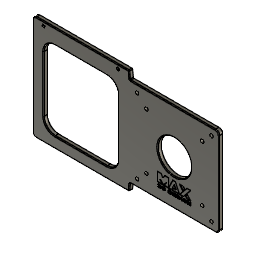
OFFSET VESA MOUNT (Autodesk Fusion 360 design; units mm, degrees)
part number: 2026-05-18-19-14-02-134
Autodesk Fusion 360 part; units mm, degrees
sketch "Sketch1" plane through (0, 0, 0) normal (0, 1, 0) x (1, 0, 0)
  line L0 (0, -120) -> (1, -120)
  line L1 (1, -120) -> (1, 0)
  line L2 (1, 0) -> (0, 0)
  line L3 (1, -120) -> (121, -120)
  line L4 (121, -120) -> (121, 0)
  line L5 (121, 0) -> (1, 0)
  line L6 (1, 0) -> (1, -120)
  line L7 (11, -110) -> (111, -110)
  line L8 (111, -110) -> (111, -10)
  line L9 (111, -10) -> (11, -10)
  line L10 (11, -10) -> (11, -110)
  line L11 (98.5, -97.5) -> (23.5, -97.5)
  line L12 (23.5, -97.5) -> (23.5, -22.5)
  line L13 (23.5, -22.5) -> (98.5, -22.5)
  line L14 (98.5, -22.5) -> (98.5, -97.5)
  line L15 (61, -97.5) -> (61, -110)
  line L16 (98.5, -60) -> (111, -60)
  line L17 (111, -60) -> (121, -60)
  line L18 (61, -120) -> (61, -110)
  line L19 (0, -120) -> (0, 0)
  line L20 (0, -130.5) -> (-129.5, -130.5)
  line L21 (-129.5, -130.5) -> (-129.5, 10.5)
  line L22 (-129.5, 10.5) -> (0, 10.5)
  line L23 (0, 10.5) -> (0, -130.5)
  line L24 (0, -130.5) -> (1, -120)
  line L25 (0, 10.5) -> (1, 0)
  circle A0 centre (61, -60) radius 22.5
  line L26 (-14.75, -125) -> (-114.75, -125)
  line L27 (-64.75, -130.5) -> (-64.75, -125)
  circle A1 centre (-114.75, -125) radius 2
  circle A2 centre (-14.75, -125) radius 2
  line L28 (-14.75, -4.5) -> (-114.75, -4.5)
  line L29 (-114.75, -4.5) -> (-114.75, -110)
  line L30 (-114.75, -110) -> (-14.75, -110)
  line L31 (-14.75, -110) -> (-14.75, -4.5)
  point P0 (122.7782, -63.5)
  point P1 (0, -60)
  point P2 (0, -60)
  dimension "d7" = 10
  dimension "d8" = 10
  dimension "d9" = 75
  dimension "d10" = 100
  dimension "d12" = 1
  dimension "d13" = 129.5
  dimension "d14" = 141
  dimension "d15" = 45
  dimension "d18" = 5.5
  dimension "d19" = 100
  dimension "d20" = 4
  dimension "d32" = 15
  dimension "d33" = 15
  constraint horizontal L0
  constraint vertical L1
  constraint horizontal L2
  constraint horizontal L3
  constraint vertical L4
  constraint horizontal L5
  constraint vertical L6
  constraint horizontal L7
  constraint vertical L8
  constraint horizontal L9
  constraint vertical L10
  constraint horizontal L11
  constraint vertical L12
  constraint horizontal L13
  constraint vertical L14
  constraint midpoint L11 L15.start
  constraint midpoint L7 L15.end
  constraint midpoint L14 L16.start
  constraint midpoint L8 L16.end
  constraint midpoint L4 L17.end
  constraint vertical L15
  constraint horizontal L16
  constraint horizontal L17
  constraint midpoint L3 L18.start
  constraint vertical L18
  constraint collinear L2 L5
  constraint equal L11 L14
  constraint equal L7 L8
  constraint perpendicular L2 L19
  constraint coincident L2.end L19.end
  constraint horizontal L20
  constraint vertical L21
  constraint horizontal L22
  constraint vertical L23
  constraint coincident L23 P2
  constraint midpoint L23 P2
  constraint midpoint L19 P2
  constraint coincident P2 P1
  constraint vertical L15.start A0.centre
  constraint horizontal L16.start A0.centre
  constraint horizontal L26
  constraint midpoint L20 L27.start
  constraint midpoint L26 L27.end
  constraint vertical L27
  constraint coincident L26.end A1.centre
  constraint coincident L26.start A2.centre
  constraint equal A1 A2
  constraint horizontal L28
  constraint vertical L29
  constraint horizontal L30
  constraint vertical L31
  constraint vertical L26.end L29.end
  constraint vertical L26.start L30.end
  measures "d7" distance of L4 L8
  measures "d8" distance of L3 L7
  measures "d9" distance of L11.start L13.end
  measures "d10" distance of L7.end L8.end
  measures "d12" distance of L0.start L0.end
  measures "d13" distance of L21.end L22.end
  measures "d14" distance of L20.end L21.end
  measures "d15" diameter of A0
  measures "d18" distance of L27.start L27.end
  measures "d19" distance of L26.start L26.end
  measures "d20" diameter of A1
  measures "d32" distance of L22 L28
  measures "d33" distance of L26 L30
extrude "Extrude1" add sketch "Sketch1" along normal blind 6
hole "Hole1" at (23.5, 0, 97.5) at (98.5, 0, 97.5) at (111, 0, 110) at (11, 0, 110) at (11, 0, 10) at (23.5, 0, 22.5) at (98.5, 0, 22.5) at (111, 0, 10) direction (0, 1, 0) diameter 4.5 depth 30 tip angle 118
fillet "Fillet1" radius 5 4 edges at (121, 3, 120) (121, 3, 0) (-129.5, 3, -10.5) (-129.5, 3, 130.5)
sketch "Sketch2" plane through (0, 6, 0) normal (0, 1, 0) x (-1, 0, 0)
  arc A0 (129.5, 125.5) -> (124.5, 130.5) centre (124.5, 125.5) ccw
  line L0 (124.5, 130.5) -> (0, 130.5)
  line L1 (0, 130.5) -> (-1, 120)
  line L2 (-1, 120) -> (-116, 120)
  arc A1 (-116, 120) -> (-121, 115) centre (-116, 115) ccw
  line L3 (-121, 115) -> (-121, 5)
  arc A2 (-121, 5) -> (-116, 0) centre (-116, 5) ccw
  line L4 (-116, 0) -> (-1, 0)
  line L5 (-1, 0) -> (0, -10.5)
  line L6 (0, -10.5) -> (124.5, -10.5)
  arc A3 (124.5, -10.5) -> (129.5, -5.5) centre (124.5, -5.5) ccw
  line L7 (129.5, -5.5) -> (129.5, 125.5)
  circle A4 centre (14.75, 125) radius 2
  circle A5 centre (-61, 60) radius 22.5
  circle A6 centre (114.75, 125) radius 2
  circle A7 centre (-111, 10) radius 2.25
  circle A8 centre (-23.5, 22.5) radius 2.25
  circle A9 centre (-11, 110) radius 2.25
  circle A10 centre (-98.5, 97.5) radius 2.25
  circle A11 centre (-23.5, 97.5) radius 2.25
  circle A12 centre (-111, 110) radius 2.25
  circle A13 centre (-11, 10) radius 2.25
  circle A14 centre (-98.5, 22.5) radius 2.25
  circle A15 centre (14.75, 125) radius 2.75
  circle A16 centre (114.75, 125) radius 2.75
  line L8 (14.75, 4.5) -> (14.75, 110)
  line L9 (14.75, 110) -> (114.75, 110)
  line L10 (114.75, 110) -> (114.75, 4.5)
  line L11 (114.75, 4.5) -> (14.75, 4.5)
  dimension "d29" = 5.5
  constraint concentric A4 A15
  constraint concentric A6 A16
  constraint equal A15 A16
  measures "d29" diameter of A15
extrude "Extrude2" cut sketch "Sketch2" against normal blind 4.5 contours A4 | A6 | A15 | A16
fillet "Fillet2" radius 15 4 edges at (-114.75, 3, 110) (-14.75, 3, 110) (-14.75, 3, 4.5) (-114.75, 3, 4.5)
fillet "Fillet3" radius 1 4 edges at (0, 3, 130.5) (1, 3, 120) (1, 3, 0) (0, 3, -10.5)
chamfer "Chamfer1" distance 1 angle 45 50 edges at (-14.75, 0, 57.25) (-19.1434, 0, 105.6066) (-64.75, 0, 110) (-110.3566, 0, 105.6066) (-114.75, 0, 57.25) (-110.3566, 0, 8.8934) (-64.75, 0, 4.5) (-19.1434, 0, 8.8934) (0.5, 0, -5.25) (1.2365, 0, -0.2601) (58.9546, 0, 0) (119.5355, 0, 1.4645) (121, 0, 60) (119.5355, 0, 118.5355) (58.9546, 0, 120) (1.2365, 0, 120.2601) (0.5, 0, 125.25) (-0.2365, 0, 130.2399) (-62.7046, 0, 130.5) (-128.0355, 0, 129.0355) (-129.5, 0, 60) (-128.0355, 0, -9.0355) (-62.7046, 0, -10.5) (-0.2365, 0, -10.2399) (0.5, 6, -5.25) (-0.2365, 6, -10.2399) (-62.7046, 6, -10.5) (-128.0355, 6, -9.0355) (-129.5, 6, 60) (-128.0355, 6, 129.0355) (-62.7046, 6, 130.5) (-0.2365, 6, 130.2399) (0.5, 6, 125.25) (1.2365, 6, 120.2601) (58.9546, 6, 120) (119.5355, 6, 118.5355) (121, 6, 60) (119.5355, 6, 1.4645) (58.9546, 6, 0) (1.2365, 6, -0.2601) (40.0226, 0, 51.8637) (40.0226, 6, 51.8637) (-14.75, 6, 57.25) (-19.1434, 6, 105.6066) (-64.75, 6, 110) (-110.3566, 6, 105.6066) (-114.75, 6, 57.25) (-110.3566, 6, 8.8934) (-64.75, 6, 4.5) (-19.1434, 6, 8.8934)
sketch "Sketch3" plane through (0, 0, 0) normal (0, -1, 0) x (1, 0, 0)
  line L0 (-0.9093, 129.5) -> (-124.5, 129.5)
  arc A0 (-124.5, 129.5) -> (-128.5, 125.5) centre (-124.5, 125.5) ccw
  line L1 (-128.5, 125.5) -> (-128.5, -5.5)
  arc A1 (-128.5, -5.5) -> (-124.5, -9.5) centre (-124.5, -5.5) ccw
  line L2 (-124.5, -9.5) -> (-0.9093, -9.5)
  line L3 (-0.9093, -9.5) -> (-0.0817, -0.8104)
  arc A2 (1.9093, 1) -> (-0.0817, -0.8104) centre (1.9093, -1) ccw
  line L4 (1.9093, 1) -> (116, 1)
  arc A3 (116, 1) -> (120, 5) centre (116, 5) ccw
  line L5 (120, 5) -> (120, 115)
  arc A4 (120, 115) -> (116, 119) centre (116, 115) ccw
  line L6 (116, 119) -> (1.9093, 119)
  arc A5 (-0.0817, 120.8104) -> (1.9093, 119) centre (1.9093, 121) ccw
  line L7 (-0.0817, 120.8104) -> (-0.9093, 129.5)
  circle A6 centre (98.5, 22.5) radius 2.25
  circle A7 centre (11, 10) radius 2.25
  circle A8 centre (111, 110) radius 2.25
  circle A9 centre (23.5, 97.5) radius 2.25
  circle A10 centre (98.5, 97.5) radius 2.25
  circle A11 centre (11, 110) radius 2.25
  circle A12 centre (23.5, 22.5) radius 2.25
  circle A13 centre (111, 10) radius 2.25
  circle A14 centre (-114.75, 125) radius 2
  circle A15 centre (-14.75, 125) radius 2
  line L8 (-13.75, 95) -> (-13.75, 19.5)
  arc A16 (-29.75, 3.5) -> (-13.75, 19.5) centre (-29.75, 19.5) ccw
  line L9 (-29.75, 3.5) -> (-99.75, 3.5)
  arc A17 (-115.75, 19.5) -> (-99.75, 3.5) centre (-99.75, 19.5) ccw
  line L10 (-115.75, 19.5) -> (-115.75, 95)
  arc A18 (-99.75, 111) -> (-115.75, 95) centre (-99.75, 95) ccw
  line L11 (-99.75, 111) -> (-29.75, 111)
  arc A19 (-13.75, 95) -> (-29.75, 111) centre (-29.75, 95) ccw
  circle A20 centre (61, 60) radius 23.5
  line L12 (43.0359, 15.5581) -> (43.0359, 15.4087)
  spline S0 degree 3 poles (43.0359, 15.4087) (43.0359, 14.8683) (42.6052, 14.478) (42.0137, 14.478) knots 0 0 0 0 1 1 1 1
  line L13 (42.0137, 14.478) -> (39.4564, 14.478)
  spline S1 degree 3 poles (39.4564, 14.478) (38.9762, 14.478) (38.6317, 14.7746) (38.6317, 15.1808) knots 0 0 0 0 1 1 1 1
  line L14 (38.6317, 15.1808) -> (38.6317, 15.5353)
  line L15 (38.6317, 15.5353) -> (40.0975, 16.0429)
  line L16 (40.0975, 16.0429) -> (40.0975, 15.6427)
  spline S2 degree 3 poles (40.0975, 15.6427) (40.0975, 15.4933) (40.2057, 15.4087) (40.3963, 15.4087) knots 0 0 0 0 1 1 1 1
  line L17 (40.3963, 15.4087) -> (41.2706, 15.4087)
  spline S3 degree 3 poles (41.2706, 15.4087) (41.4611, 15.4087) (41.5694, 15.4933) (41.5694, 15.6427) knots 0 0 0 0 1 1 1 1
  line L18 (41.5694, 15.6427) -> (41.5694, 15.7403)
  spline S4 degree 3 poles (41.5694, 15.7403) (41.5694, 15.8897) (41.4611, 15.9743) (41.2706, 15.9743) knots 0 0 0 0 1 1 1 1
  line L19 (41.2706, 15.9743) -> (40.6166, 15.9743)
  line L20 (40.6166, 15.9743) -> (40.6166, 16.69)
  line L21 (40.6166, 16.69) -> (41.1722, 16.69)
  spline S5 degree 3 poles (41.1722, 16.69) (41.3628, 16.69) (41.471, 16.7747) (41.471, 16.9241) knots 0 0 0 0 1 1 1 1
  line L22 (41.471, 16.9241) -> (41.471, 17.0216)
  spline S6 degree 3 poles (41.471, 17.0216) (41.471, 17.171) (41.3628, 17.2556) (41.1722, 17.2556) knots 0 0 0 0 1 1 1 1
  line L23 (41.1722, 17.2556) -> (40.3963, 17.2556)
  spline S7 degree 3 poles (40.3963, 17.2556) (40.2057, 17.2556) (40.0975, 17.171) (40.0975, 17.0216) knots 0 0 0 0 1 1 1 1
  line L24 (40.0975, 17.0216) -> (40.0975, 16.8494)
  line L25 (40.0975, 16.8494) -> (38.6317, 17.357)
  line L26 (38.6317, 17.357) -> (38.6317, 17.4843)
  spline S8 degree 3 poles (38.6317, 17.4843) (38.6317, 17.8913) (38.977, 18.1871) (39.4564, 18.1871) knots 0 0 0 0 1 1 1 1
  line L27 (39.4564, 18.1871) -> (41.9482, 18.184)
  spline S9 degree 3 poles (41.9482, 18.184) (42.5397, 18.184) (42.9376, 17.7938) (42.9376, 17.2533) knots 0 0 0 0 1 1 1 1
  line L28 (42.9376, 17.2533) -> (42.9376, 17.0094)
  spline S10 degree 3 poles (42.9376, 17.0094) (42.9376, 16.6611) (42.76, 16.456) (42.481, 16.3455) knots 0 0 0 0 1 1 1 1
  spline S11 degree 3 poles (42.481, 16.3455) (42.8026, 16.2312) (43.0359, 15.9972) (43.0359, 15.5581) knots 0 0 0 0 1 1 1 1
  line L29 (48.7557, 17.2564) -> (48.7557, 15.4011)
  spline S12 degree 3 poles (48.7557, 15.4011) (48.7557, 14.8645) (48.325, 14.4773) (47.7335, 14.4773) knots 0 0 0 0 1 1 1 1
  line L30 (47.7335, 14.4773) -> (44.3515, 14.4773)
  line L31 (44.3515, 14.4773) -> (44.3515, 18.1871)
  line L32 (44.3515, 18.1871) -> (47.7335, 18.1871)
  spline S13 degree 3 poles (47.7335, 18.1871) (48.325, 18.1871) (48.7557, 17.7968) (48.7557, 17.2564) knots 0 0 0 0 1 1 1 1
  spline S14 degree 3 poles (47.2899, 16.876) (47.2899, 17.0384) (47.158, 17.1558) (46.9774, 17.1558) knots 0 0 0 0 1 1 1 1
  line L33 (46.9774, 17.1558) -> (45.85, 17.1626)
  line L34 (45.85, 17.1626) -> (45.85, 15.5033)
  line L35 (45.85, 15.5033) -> (46.9774, 15.5033)
  spline S15 degree 3 poles (46.9774, 15.5033) (47.158, 15.5033) (47.2899, 15.6168) (47.2899, 15.7769) knots 0 0 0 0 1 1 1 1
  line L36 (47.2899, 15.7769) -> (47.2899, 16.876)
  line L37 (57.0068, 17.2564) -> (57.0068, 15.4011)
  spline S16 degree 3 poles (57.0068, 15.4011) (57.0068, 14.8645) (56.5762, 14.4773) (55.9847, 14.4773) knots 0 0 0 0 1 1 1 1
  line L38 (55.9847, 14.4773) -> (52.6027, 14.4773)
  line L39 (52.6027, 14.4773) -> (52.6027, 18.1871)
  line L40 (52.6027, 18.1871) -> (55.9847, 18.1871)
  spline S17 degree 3 poles (55.9847, 18.1871) (56.5762, 18.1871) (57.0068, 17.7968) (57.0068, 17.2564) knots 0 0 0 0 1 1 1 1
  spline S18 degree 3 poles (55.5403, 16.876) (55.5403, 17.0384) (55.4084, 17.1558) (55.2278, 17.1558) knots 0 0 0 0 1 1 1 1
  line L41 (55.2278, 17.1558) -> (54.1004, 17.1626)
  line L42 (54.1004, 17.1626) -> (54.1004, 15.5033)
  line L43 (54.1004, 15.5033) -> (55.2278, 15.5033)
  spline S19 degree 3 poles (55.2278, 15.5033) (55.4084, 15.5033) (55.5403, 15.6168) (55.5403, 15.7769) knots 0 0 0 0 1 1 1 1
  line L44 (55.5403, 15.7769) -> (55.5403, 16.876)
  line L45 (58.5526, 18.1871) -> (62.6938, 18.1871)
  line L46 (62.6938, 18.1871) -> (62.6938, 17.2274)
  line L47 (62.6938, 17.2274) -> (60.0512, 17.2274)
  line L48 (60.0512, 17.2274) -> (60.0512, 16.7716)
  line L49 (60.0512, 16.7716) -> (61.7738, 16.7716)
  line L50 (61.7738, 16.7716) -> (61.7738, 15.8928)
  line L51 (61.7738, 15.8928) -> (60.0512, 15.8928)
  line L52 (60.0512, 15.8928) -> (60.0512, 15.4369)
  line L53 (60.0512, 15.4369) -> (62.6938, 15.4369)
  line L54 (62.6938, 15.4369) -> (62.6938, 14.4773)
  line L55 (62.6938, 14.4773) -> (58.5526, 14.4773)
  line L56 (58.5526, 14.4773) -> (58.5526, 18.1871)
  line L57 (63.9104, 15.1801) -> (63.9104, 15.2776)
  line L58 (63.9104, 15.2776) -> (65.3761, 15.7853)
  line L59 (65.3761, 15.7853) -> (65.3761, 15.5772)
  spline S20 degree 3 poles (65.3761, 15.5772) (65.3761, 15.4278) (65.4844, 15.3432) (65.6749, 15.3432) knots 0 0 0 0 1 1 1 1
  line L60 (65.6749, 15.3432) -> (66.5462, 15.3432)
  spline S21 degree 3 poles (66.5462, 15.3432) (66.7367, 15.3432) (66.845, 15.4278) (66.845, 15.5772) knots 0 0 0 0 1 1 1 1
  line L61 (66.845, 15.5772) -> (66.845, 15.6488)
  spline S22 degree 3 poles (66.845, 15.6488) (66.845, 15.7982) (66.7367, 15.8828) (66.5462, 15.8828) knots 0 0 0 0 1 1 1 1
  line L62 (66.5462, 15.8828) -> (64.9325, 15.8828)
  spline S23 degree 3 poles (64.9325, 15.8828) (64.341, 15.8828) (63.9104, 16.2731) (63.9104, 16.8135) knots 0 0 0 0 1 1 1 1
  line L63 (63.9104, 16.8135) -> (63.9104, 17.4835)
  spline S24 degree 3 poles (63.9104, 17.4835) (63.9104, 17.8906) (64.2519, 18.1863) (64.729, 18.1863) knots 0 0 0 0 1 1 1 1
  line L64 (64.729, 18.1863) -> (67.4898, 18.1863)
  spline S25 degree 3 poles (67.4898, 18.1863) (67.97, 18.1863) (68.3145, 17.8898) (68.3145, 17.4835) knots 0 0 0 0 1 1 1 1
  line L65 (68.3145, 17.4835) -> (68.3145, 17.386)
  line L66 (68.3145, 17.386) -> (66.8488, 16.8783)
  line L67 (66.8488, 16.8783) -> (66.8488, 17.0864)
  spline S26 degree 3 poles (66.8488, 17.0864) (66.8488, 17.2358) (66.7405, 17.3204) (66.55, 17.3204) knots 0 0 0 0 1 1 1 1
  line L68 (66.55, 17.3204) -> (65.6787, 17.3204)
  spline S27 degree 3 poles (65.6787, 17.3204) (65.4882, 17.3204) (65.38, 17.2358) (65.38, 17.0864) knots 0 0 0 0 1 1 1 1
  line L69 (65.38, 17.0864) -> (65.38, 17.0148)
  spline S28 degree 3 poles (65.38, 17.0148) (65.38, 16.8654) (65.4882, 16.7808) (65.6787, 16.7808) knots 0 0 0 0 1 1 1 1
  line L70 (65.6787, 16.7808) -> (67.2924, 16.7808)
  spline S29 degree 3 poles (67.2924, 16.7808) (67.8839, 16.7808) (68.3145, 16.3905) (68.3145, 15.8501) knots 0 0 0 0 1 1 1 1
  line L71 (68.3145, 15.8501) -> (68.3145, 15.1793)
  spline S30 degree 3 poles (68.3145, 15.1793) (68.3145, 14.7723) (67.9693, 14.4765) (67.4959, 14.4765) knots 0 0 0 0 1 1 1 1
  line L72 (67.4959, 14.4765) -> (64.7351, 14.4765)
  spline S31 degree 3 poles (64.7351, 14.4765) (64.2557, 14.4773) (63.9104, 14.7738) (63.9104, 15.1801) knots 0 0 0 0 1 1 1 1
  line L73 (69.762, 18.1871) -> (71.2606, 18.1871)
  line L74 (71.2606, 18.1871) -> (71.2606, 14.4773)
  line L75 (71.2606, 14.4773) -> (69.762, 14.4773)
  line L76 (69.762, 14.4773) -> (69.762, 18.1871)
  line L77 (72.8056, 15.174) -> (72.8056, 17.4843)
  spline S32 degree 3 poles (72.8056, 17.4843) (72.8056, 17.8913) (73.1509, 18.1871) (73.6243, 18.1871) knots 0 0 0 0 1 1 1 1
  line L78 (73.6243, 18.1871) -> (76.3851, 18.1871)
  spline S33 degree 3 poles (76.3851, 18.1871) (76.8645, 18.1871) (77.2098, 17.8906) (77.2098, 17.4843) knots 0 0 0 0 1 1 1 1
  line L79 (77.2098, 17.4843) -> (77.2098, 17.3928)
  line L80 (77.2098, 17.3928) -> (75.744, 16.8852)
  spline S34 degree 3 poles (75.744, 16.8852) (75.744, 17.0445) (75.616, 17.1588) (75.4384, 17.1588) knots 0 0 0 0 1 1 1 1
  line L81 (75.4384, 17.1588) -> (74.577, 17.1588)
  spline S35 degree 3 poles (74.577, 17.1588) (74.3994, 17.1588) (74.2714, 17.0414) (74.2714, 16.8791) knots 0 0 0 0 1 1 1 1
  line L82 (74.2714, 16.8791) -> (74.2714, 15.7792)
  spline S36 degree 3 poles (74.2714, 15.7792) (74.2714, 15.6199) (74.3994, 15.5055) (74.577, 15.5055) knots 0 0 0 0 1 1 1 1
  line L83 (74.577, 15.5055) -> (75.4315, 15.5055)
  spline S37 degree 3 poles (75.4315, 15.5055) (75.6122, 15.5055) (75.744, 15.6191) (75.744, 15.7792) knots 0 0 0 0 1 1 1 1
  line L84 (75.744, 15.7792) -> (75.744, 15.9873)
  line L85 (75.744, 15.9873) -> (74.9422, 15.9873)
  line L86 (74.9422, 15.9873) -> (75.1723, 16.4034)
  line L87 (75.1723, 16.4034) -> (77.2106, 16.4034)
  line L88 (77.2106, 16.4034) -> (77.2106, 15.1732)
  spline S38 degree 3 poles (77.2106, 15.1732) (77.2106, 14.77) (76.8653, 14.4765) (76.3858, 14.4765) knots 0 0 0 0 1 1 1 1
  line L89 (76.3858, 14.4765) -> (73.625, 14.4765)
  spline S39 degree 3 poles (73.625, 14.4765) (73.1509, 14.4773) (72.8056, 14.77) (72.8056, 15.174) knots 0 0 0 0 1 1 1 1
  line L90 (83.1278, 18.1871) -> (83.1278, 14.4773)
  line L91 (83.1278, 14.4773) -> (81.4973, 14.4773)
  line L92 (81.4973, 14.4773) -> (80.0903, 16.5925)
  line L93 (80.0903, 16.5925) -> (80.0903, 14.4773)
  line L94 (80.0903, 14.4773) -> (78.7228, 14.4773)
  line L95 (78.7228, 14.4773) -> (78.7228, 18.1871)
  line L96 (78.7228, 18.1871) -> (80.3532, 18.1871)
  line L97 (80.3532, 18.1871) -> (81.7634, 16.0391)
  line L98 (81.7634, 16.0391) -> (81.7634, 18.1871)
  line L99 (81.7634, 18.1871) -> (83.1278, 18.1871)
  line L100 (38.2872, 32.2137) -> (38.2697, 20.226)
  line L101 (38.2697, 20.226) -> (44.459, 20.2253)
  line L102 (44.459, 20.2253) -> (41.5594, 24.9107)
  line L103 (41.5594, 24.9107) -> (45.6953, 20.3907)
  line L104 (45.6953, 20.3907) -> (50.2733, 24.9222)
  line L105 (50.2733, 24.9222) -> (46.9263, 20.2413)
  line L106 (46.9263, 20.2413) -> (53.0737, 20.2253)
  line L107 (53.0737, 20.2253) -> (53.153, 32.2083)
  line L108 (53.153, 32.2083) -> (48.1596, 32.2083)
  line L109 (48.1596, 32.2083) -> (45.6526, 28.1982)
  line L110 (45.6526, 28.1982) -> (43.2257, 32.2563)
  line L111 (43.2257, 32.2563) -> (38.2872, 32.2137)
  line L112 (53.14, 20.2245) -> (58.7241, 32.2411)
  line L113 (58.7241, 32.2411) -> (62.408, 32.2861)
  line L114 (62.408, 32.2861) -> (67.9967, 20.2725)
  line L115 (67.9967, 20.2725) -> (58.1334, 20.2428)
  line L116 (58.1334, 20.2428) -> (59.4475, 23.2407)
  line L117 (59.4475, 23.2407) -> (63.0795, 23.2696)
  line L118 (63.0795, 23.2696) -> (60.4948, 27.7165)
  line L119 (60.4948, 27.7165) -> (57.2043, 20.2512)
  line L120 (57.2043, 20.2512) -> (53.14, 20.2245)
  line L121 (68.0866, 20.2802) -> (77.9164, 32.2701)
  line L122 (77.9164, 32.2701) -> (82.9364, 32.2701)
  line L123 (82.9364, 32.2701) -> (72.9428, 20.1956)
  line L124 (72.9428, 20.1956) -> (68.0866, 20.2802)
  line L125 (68.0356, 32.155) -> (72.301, 26.6997)
  line L126 (72.301, 26.6997) -> (74.7684, 29.7044)
  line L127 (74.7684, 29.7044) -> (72.9779, 32.2213)
  line L128 (72.9779, 32.2213) -> (68.0356, 32.155)
  line L129 (78.0292, 20.1811) -> (75.9978, 22.6042)
  line L130 (75.9978, 22.6042) -> (78.3448, 25.3406)
  line L131 (78.3448, 25.3406) -> (82.9281, 20.1666)
  line L132 (82.9281, 20.1666) -> (78.0292, 20.1811)
extrude "Extrude3" cut sketch "Sketch3" against normal blind 0.5 contours L12 S0 L13 S1 L14 L15 L16 S2 L17 S3 L18 S4 L19 L20 L21 S5 L22 S6 L23 S7 L24 L25 L26 S8 L27 S9 L28 S10 S11 | L29 S12 L30 L31 L32 S13 | L37 S16 L38 L39 L40 S17 | L45 L46 L47 L48 L49 L50 L51 L52 L53 L54 L55 L56 | L57 L58 L59 S20 L60 S21 L61 S22 L62 S23 L63 S24 L64 S25 L65 L66 L67 S26 L68 S27 L69 S28 L70 S29 L71 S30 L72 S31 | L73 L74 L75 L76 | L77 S32 L78 S33 L79 L80 S34 L81 S35 L82 S36 L83 S37 L84 L85 L86 L87 L88 S38 L89 S39 | L90 L91 L92 L93 L94 L95 L96 L97 L98 L99 | L100 L101 L102 L103 L104 L105 L106 L107 L108 L109 L110 L111 | L112 L113 L114 L115 L116 L117 L118 L119 L120 | L121 L122 L123 L124 | L125 L126 L127 L128 | L129 L130 L131 L132
equation "PC_WIDTH = 129.5 mm"
equation "PC_HEIGHT_BRACKET = 141 mm"
equation "HOLE_DIA = 4 mm"
equation "TOP_PC_TO_HOLE_CENTER = 5.5 mm"
equation "HOLE_SPACING = 100 mm"
equation "d8 = d7"
equation "d13 = PC_WIDTH"
equation "d14 = PC_HEIGHT_BRACKET"
equation "d16 = THICKNESS"
equation "d18 = TOP_PC_TO_HOLE_CENTER"
equation "d19 = HOLE_SPACING"
equation "d20 = HOLE_DIA"
equation "COUNTERBORE_DIA = 5.5 mm"
equation "COUNTERBORE_DEPTH = THICKNESS - 1.5 mm"
equation "THICKNESS = 6 mm"
equation "d29 = COUNTERBORE_DIA"
equation "d30 = -COUNTERBORE_DEPTH"
